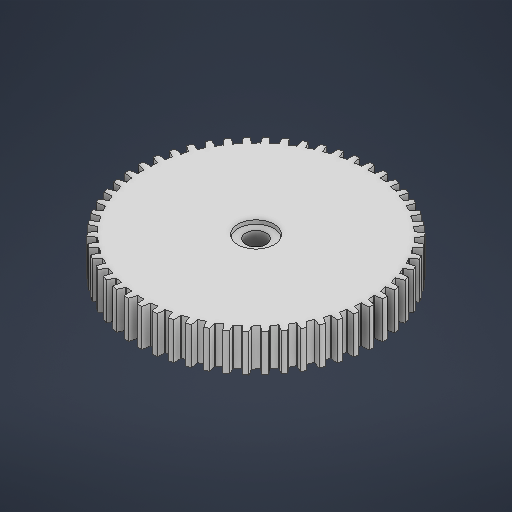
# Autodesk Inventor part: Servo Wheel
Saved by Autodesk Inventor 2027 (Build 310192060, 192F)
## iProperties
Created: 2026-10-23
Part Number: Servo Wheel
Material: Generic
Document SubType Name: Modeling
Designer: troop
Density: 1 g/cm^3
Appearance: Default
Author: troop
Autodesk Inventor part; units mm, degrees
(part 1 of 2)
ref_plane "YZ Plane" through (0, 0, 0) normal (1, 0, 0) x (0, 1, 0)
ref_plane "XZ Plane" through (0, 0, 0) normal (0, 1, 0) x (-1, 0, 0)
sketch "Sketch1" plane through (0, 0, 0) normal (0, 1, 0) x (-1, 0, 0)
  circle A0 centre (0, 0) radius 15
  dimension "d0" = 30
  constraints: 1 centre point, 1 coincident
  measures "d0" diameter of A0
extrude "Extrusion1" add sketch "Sketch1" along normal blind 5
sketch "Sketch2" plane through (0, 0, 0) normal (0, -1, 0) x (1, 0, 0)
  line L0 (-2.242, 0) -> (-2.6661, 0.4202)
  line L1 (-2.242, 0) -> (-2.6619, -0.4271)
  line L2 (-2.1323, -0.6928) -> (-2.6654, -0.4242)
  line L3 (-2.1323, -0.6928) -> (-2.3997, -1.2288)
  line L4 (-1.8138, -1.3178) -> (-2.4039, -1.2272)
  line L5 (-1.8138, -1.3178) -> (-1.9025, -1.9102)
  line L6 (-1.3178, -1.8138) -> (-1.907, -1.9099)
  line L7 (-1.3178, -1.8138) -> (-1.2191, -2.4046)
  line L8 (-0.6928, -2.1323) -> (-1.2235, -2.4058)
  line L9 (-0.6928, -2.1323) -> (-0.4164, -2.6637)
  line L10 (0, -2.242) -> (-0.4202, -2.6661)
  line L11 (0, -2.242) -> (0.4271, -2.6619)
  line L12 (0.6928, -2.1323) -> (0.4242, -2.6654)
  line L13 (0.6928, -2.1323) -> (1.2288, -2.3997)
  line L14 (1.3178, -1.8138) -> (1.2272, -2.4039)
  line L15 (1.3178, -1.8138) -> (1.9102, -1.9025)
  line L16 (1.8138, -1.3178) -> (1.9099, -1.907)
  line L17 (1.8138, -1.3178) -> (2.4046, -1.2191)
  line L18 (2.1323, -0.6928) -> (2.4058, -1.2235)
  line L19 (2.1323, -0.6928) -> (2.6637, -0.4164)
  line L20 (2.242, 0) -> (2.6661, -0.4202)
  line L21 (2.242, 0) -> (2.6619, 0.4271)
  line L22 (2.1323, 0.6928) -> (2.6654, 0.4242)
  line L23 (2.1323, 0.6928) -> (2.3997, 1.2288)
  line L24 (1.8138, 1.3178) -> (2.4039, 1.2272)
  line L25 (1.8138, 1.3178) -> (1.9025, 1.9102)
  line L26 (1.3178, 1.8138) -> (1.907, 1.9099)
  line L27 (1.3178, 1.8138) -> (1.2191, 2.4046)
  line L28 (0.6928, 2.1323) -> (1.2235, 2.4058)
  line L29 (0.6928, 2.1323) -> (0.4164, 2.6637)
  line L30 (0, 2.242) -> (0.4202, 2.6661)
  line L31 (0, 2.242) -> (-0.4271, 2.6619)
  line L32 (-0.6928, 2.1323) -> (-0.4242, 2.6654)
  line L33 (-0.6928, 2.1323) -> (-1.2288, 2.3997)
  line L34 (-1.3178, 1.8138) -> (-1.2272, 2.4039)
  line L35 (-1.3178, 1.8138) -> (-1.9102, 1.9025)
  line L36 (-1.8138, 1.3178) -> (-1.9099, 1.907)
  line L37 (-1.8138, 1.3178) -> (-2.4046, 1.2191)
  line L38 (-2.1323, 0.6928) -> (-2.4058, 1.2235)
  line L39 (-2.1323, 0.6928) -> (-2.6637, 0.4164)
  point P0 (0, 0)
  point P1 (-2.6627, 0.4168)
  point P2 (-2.6612, -0.4264)
  point P3 (-2.3992, -1.2279)
  point P4 (-1.9023, -1.9092)
  point P5 (-1.2193, -2.4036)
  point P6 (-0.4168, -2.6627)
  point P7 (0.4264, -2.6612)
  point P8 (1.2279, -2.3992)
  point P9 (1.9092, -1.9023)
  point P10 (2.4036, -1.2193)
  point P11 (2.6627, -0.4168)
  point P12 (2.6612, 0.4264)
  point P13 (2.3992, 1.2279)
  point P14 (1.9023, 1.9092)
  point P15 (1.2193, 2.4036)
  point P16 (0.4168, 2.6627)
  point P17 (-0.4264, 2.6612)
  point P18 (-1.2279, 2.3992)
  point P19 (-1.9092, 1.9023)
  point P20 (-2.4036, 1.2193)
  dimension "d3" = 2.242
  dimension "d5" = 2.699
  dimension "d6" = 0.597
  dimension "d7" = 0
  dimension "d8" = 0.599
  dimension "d9" = 2.696
  dimension "d12" = 360
  constraints: 80 end point, 101 other
  measures "d3" distance of point (0, 0) L0.start
  measures "d5" distance of L0.end point (0, 0)
  measures "d6" distance of L0.start L0.end
  measures "d7" vertical distance of point (0, 0) L0.start
  measures "d8" distance of L0.start L1.end
  measures "d9" distance of point (0, 0) L1.end
ref_plane "Work Plane1" through (0, 2, 0) normal (0, -1, 0) x (1, 0, 0)
sketch "Sketch3" plane through (0, 2, 0) normal (0, -1, 0) x (1, 0, 0)
  circle A0 centre (0, 0) radius 1.3518
  dimension "d16" = 2.7035
  constraints: 1 centre point, 1 coincident
  measures "d16" diameter of A0
sketch "Sketch4" plane through (0, 5, 0) normal (0, 1, 0) x (1, 0, 0)
  circle A0 centre (0, 0) radius 2.398
  dimension "d19" = 4.796
  constraints: 1 centre point, 1 coincident
  measures "d19" diameter of A0
sketch "Sketch5" plane through (0, 5, 0) normal (0, 1, 0) x (1, 0, 0)
  line L0 (15.0507, 0.0003) -> (14.984, 0.8109)
  line L1 (15.0507, 0.0003) -> (14.9793, -0.8668)
  arc A0 (15.0506, 0.035) -> (15.0877, -0.0001) centre (15.108, 0.0585) ccw
  arc A1 (16.0355, -0.2257) -> (15.0877, -0.0001) centre (14.1946, -5.8554) ccw
  line L2 (15.0877, -0.0001) -> (15.016, -0.8698)
  arc A2 (15.016, -0.8698) -> (15.9859, -0.828) centre (15.2464, 5.0487) ccw
  line L3 (16.0355, -0.2257) -> (15.9859, -0.828)
  line L4 (14.9793, -0.8668) -> (14.975, -0.9188)
  arc A3 (15.016, -0.8698) -> (14.965, -0.9233) centre (15.0507, -0.954) ccw
  line L5 (14.984, 0.8109) -> (14.9832, 0.8205)
  line L6 (14.9832, 0.8205) -> (14.9811, 0.8459)
  arc A4 (15.0467, 0.0489) -> (15.0506, 0.035) centre (15.108, 0.0585) ccw
  line L7 (14.9786, 0.8781) -> (14.9804, 0.8259)
  arc A5 (15.0154, 0.8793) -> (14.971, 0.8203) centre (15.0597, 0.7998) ccw
  arc A6 (15.0154, 0.8793) -> (15.9739, 1.0335) centre (14.5572, 6.7846) ccw
  line L8 (14.9489, 1.7476) -> (14.9786, 0.8781)
  line L9 (14.9857, 1.7515) -> (15.0154, 0.8793)
  line L10 (15.9533, 1.6374) -> (15.9739, 1.0335)
  arc A7 (14.9448, 1.782) -> (14.9857, 1.7515) centre (14.999, 1.812) ccw
  arc A8 (14.9393, 1.7954) -> (14.9448, 1.782) centre (14.999, 1.812) ccw
  arc A9 (15.9533, 1.6374) -> (14.9857, 1.7515) centre (14.7783, -4.1679) ccw
  line L11 (14.9489, 1.7476) -> (14.7885, 2.545)
  line L12 (14.7885, 2.545) -> (14.7866, 2.5544)
  line L13 (14.7866, 2.5544) -> (14.7816, 2.5794)
  line L14 (14.7754, 2.611) -> (14.7832, 2.5594)
  arc A10 (14.8118, 2.6166) -> (14.7745, 2.5528) centre (14.865, 2.5427) ccw
  arc A11 (14.8118, 2.6166) -> (15.7459, 2.8809) centre (13.6711, 8.4287) ccw
  line L15 (14.645, 3.4712) -> (14.7754, 2.611)
  line L16 (14.681, 3.4794) -> (14.8118, 2.6166)
  line L17 (15.6553, 3.4784) -> (15.7459, 2.8809)
  arc A12 (14.6368, 3.5049) -> (14.681, 3.4794) centre (14.6872, 3.5411) ccw
  arc A13 (14.6299, 3.5176) -> (14.6368, 3.5049) centre (14.6872, 3.5411) ccw
  arc A14 (15.6553, 3.4784) -> (14.681, 3.4794) centre (15.1623, -2.424) ccw
  line L18 (14.645, 3.4712) -> (14.3931, 4.2446)
  line L19 (14.3931, 4.2446) -> (14.3901, 4.2538)
  line L20 (14.3901, 4.2538) -> (14.3822, 4.278)
  line L21 (14.3724, 4.3087) -> (14.3861, 4.2583)
  arc A15 (14.4079, 4.3184) -> (14.3783, 4.2507) centre (14.4693, 4.2512) ccw
  arc A16 (14.4079, 4.3184) -> (15.305, 4.6895) centre (12.6002, 9.9588) ccw
  line L22 (14.143, 5.1479) -> (14.3724, 4.3087)
  line L23 (14.1778, 5.1602) -> (14.4079, 4.3184)
  line L24 (15.1456, 5.2723) -> (15.305, 4.6895)
  arc A17 (14.131, 5.1805) -> (14.1778, 5.1602) centre (14.1768, 5.2222) ccw
  arc A18 (14.1226, 5.1922) -> (14.131, 5.1805) centre (14.1768, 5.2222) ccw
  arc A19 (15.1456, 5.2723) -> (14.1778, 5.1602) centre (15.3412, -0.6474) ccw
  line L25 (14.143, 5.1479) -> (13.803, 5.8868)
  line L26 (13.803, 5.8868) -> (13.799, 5.8956)
  line L27 (13.799, 5.8956) -> (13.7883, 5.9187)
  line L28 (13.775, 5.9481) -> (13.7945, 5.8997)
  arc A20 (13.8092, 5.9619) -> (13.7876, 5.8912) centre (13.8779, 5.9022) ccw
  arc A21 (13.8092, 5.9619) -> (14.6571, 6.4345) centre (11.3588, 11.3542) ccw
  line L29 (13.4497, 6.755) -> (13.775, 5.9481)
  line L30 (13.4829, 6.7713) -> (13.8092, 5.9619)
  line L31 (14.4311, 6.995) -> (14.6571, 6.4345)
  arc A22 (13.434, 6.786) -> (13.4829, 6.7713) centre (13.4747, 6.8327) ccw
  arc A23 (13.4243, 6.7966) -> (13.434, 6.786) centre (13.4747, 6.8327) ccw
  arc A24 (14.4311, 6.995) -> (13.4829, 6.7713) centre (15.3126, 1.138) ccw
  line L32 (13.4497, 6.755) -> (13.0262, 7.4495)
  line L33 (13.0262, 7.4495) -> (13.0212, 7.4577)
  line L34 (13.0212, 7.4577) -> (13.008, 7.4794)
  line L35 (12.9913, 7.507) -> (13.0163, 7.4612)
  arc A25 (13.0237, 7.5247) -> (13.0104, 7.452) centre (13.0989, 7.4735) ccw
  arc A26 (13.0237, 7.5247) -> (13.811, 8.0926) centre (9.9639, 12.5961) ccw
  line L36 (12.5745, 8.2707) -> (12.9913, 7.507)
  line L37 (12.6056, 8.2907) -> (13.0237, 7.5247)
  line L38 (13.5215, 8.6231) -> (13.811, 8.0926)
  arc A27 (12.5554, 8.2997) -> (12.6056, 8.2907) centre (12.5904, 8.3508) ccw
  arc A28 (12.5445, 8.3091) -> (12.5554, 8.2997) centre (12.5904, 8.3508) ccw
  arc A29 (13.5215, 8.6231) -> (12.6056, 8.2907) centre (15.077, 2.9079) ccw
  line L39 (12.5745, 8.2707) -> (12.0733, 8.9114)
  line L40 (12.0733, 8.9114) -> (12.0674, 8.9189)
  line L41 (12.0674, 8.9189) -> (12.0517, 8.939)
  line L42 (12.0319, 8.9645) -> (12.0621, 8.9219)
  arc A30 (12.062, 8.9858) -> (12.0573, 8.912) centre (12.1427, 8.9436) ccw
  arc A31 (12.062, 8.9858) -> (12.7781, 9.6413) centre (8.4342, 13.6677) ccw
  line L43 (11.5293, 9.6746) -> (12.0319, 8.9645)
  line L44 (11.5579, 9.6981) -> (12.062, 8.9858)
  line L45 (12.429, 10.1345) -> (12.7781, 9.6413)
  arc A32 (11.5069, 9.7011) -> (11.5579, 9.6981) centre (11.5358, 9.756) ccw
  arc A33 (11.495, 9.7093) -> (11.5069, 9.7011) centre (11.5358, 9.756) ccw
  arc A34 (12.429, 10.1345) -> (11.5579, 9.6981) centre (14.6374, 4.6386) ccw
  line L46 (11.5293, 9.6746) -> (10.9571, 10.2527)
  line L47 (10.9571, 10.2527) -> (10.9504, 10.2596)
  line L48 (10.9504, 10.2596) -> (10.9325, 10.2777)
  line L49 (10.9099, 10.3007) -> (10.9448, 10.2619)
  arc A35 (10.9373, 10.3253) -> (10.9412, 10.2515) centre (11.0223, 10.2928) ccw
  arc A36 (10.9373, 10.3253) -> (11.5724, 11.0595) centre (6.7904, 14.5544) ccw
  line L50 (10.3282, 10.9477) -> (10.9099, 10.3007)
  line L51 (10.3539, 10.9743) -> (10.9373, 10.3253)
  line L52 (11.1684, 11.5089) -> (11.5724, 11.0595)
  arc A37 (10.3029, 10.9714) -> (10.3539, 10.9743) centre (10.3252, 11.0293) ccw
  arc A38 (10.2901, 10.9781) -> (10.3029, 10.9714) centre (10.3252, 11.0293) ccw
  arc A39 (11.1684, 11.5089) -> (10.3539, 10.9743) centre (13.9999, 6.3065) ccw
  line L53 (10.3282, 10.9477) -> (9.6928, 11.4554)
  line L54 (9.6928, 11.4554) -> (9.6853, 11.4615)
  line L55 (9.6853, 11.4615) -> (9.6654, 11.4774)
  line L56 (9.6403, 11.4976) -> (9.6794, 11.4631)
  arc A40 (9.6646, 11.5253) -> (9.6771, 11.4524) centre (9.7528, 11.5028) ccw
  arc A41 (9.6646, 11.5253) -> (10.2102, 12.3282) centre (5.0548, 15.2443) ccw
  line L57 (8.9874, 12.0727) -> (9.6403, 11.4976)
  line L58 (9.0098, 12.1021) -> (9.6646, 11.5253)
  line L59 (9.7568, 12.7276) -> (10.2102, 12.3282)
  arc A42 (8.9595, 12.0933) -> (9.0098, 12.1021) centre (8.9749, 12.1534) ccw
  arc A43 (8.9461, 12.0985) -> (8.9595, 12.0933) centre (8.9749, 12.1534) ccw
  arc A44 (9.7568, 12.7276) -> (9.0098, 12.1021) centre (13.1731, 7.8892) ccw
  line L60 (8.9874, 12.0727) -> (8.2974, 12.5033)
  line L61 (8.2974, 12.5033) -> (8.2892, 12.5084)
  line L62 (8.2892, 12.5084) -> (8.2676, 12.5218)
  line L63 (8.2403, 12.539) -> (8.2832, 12.5093)
  arc A45 (8.2613, 12.5693) -> (8.2821, 12.4984) centre (8.3515, 12.5573) ccw
  arc A46 (8.2613, 12.5693) -> (8.71, 13.4302) centre (3.2509, 15.7281) ccw
  line L64 (7.5251, 13.0344) -> (8.2403, 12.539)
  line L65 (7.5439, 13.0663) -> (8.2613, 12.5693)
  line L66 (8.2132, 13.7743) -> (8.71, 13.4302)
  arc A47 (7.495, 13.0517) -> (7.5439, 13.0663) centre (7.5033, 13.1131) ccw
  arc A48 (7.481, 13.0553) -> (7.495, 13.0517) centre (7.5033, 13.1131) ccw
  arc A49 (8.2132, 13.7743) -> (7.5439, 13.0663) centre (12.1682, 9.3652) ccw
  line L67 (7.5251, 13.0344) -> (6.7897, 13.382)
  line L68 (6.7897, 13.382) -> (6.781, 13.3861)
  line L69 (6.781, 13.3861) -> (6.758, 13.397)
  line L70 (6.7289, 13.4109) -> (6.775, 13.3863)
  arc A50 (6.7462, 13.4434) -> (6.7751, 13.3754) centre (6.8372, 13.4419) ccw
  arc A51 (6.7462, 13.4434) -> (7.0919, 14.3505) centre (1.403, 15.9992) ccw
  line L71 (5.961, 13.8199) -> (6.7289, 13.4109)
  line L72 (5.976, 13.8537) -> (6.7462, 13.4434)
  line L73 (6.5586, 14.6346) -> (7.0919, 14.3505)
  arc A52 (5.9291, 13.8336) -> (5.976, 13.8537) centre (5.9303, 13.8955) ccw
  arc A53 (5.9148, 13.8355) -> (5.9291, 13.8336) centre (5.9303, 13.8955) ccw
  arc A54 (6.5586, 14.6346) -> (5.976, 13.8537) centre (10.9987, 10.7145) ccw
  line L74 (5.961, 13.8199) -> (5.1902, 14.0797)
  line L75 (5.1902, 14.0797) -> (5.1811, 14.0828)
  line L76 (5.1811, 14.0828) -> (5.157, 14.0909)
  line L77 (5.1265, 14.1014) -> (5.1751, 14.0823)
  arc A55 (5.1399, 14.1357) -> (5.1765, 14.0715) centre (5.2305, 14.1448) ccw
  arc A56 (5.1399, 14.1357) -> (5.378, 15.0768) centre (-0.4639, 16.0539) ccw
  line L78 (4.3163, 14.4185) -> (5.1265, 14.1014)
  line L79 (4.3273, 14.4538) -> (5.1399, 14.1357)
  line L80 (4.8153, 15.2971) -> (5.378, 15.0768)
  arc A57 (4.283, 14.4284) -> (4.3273, 14.4538) centre (4.277, 14.4901) ccw
  arc A58 (4.2686, 14.4286) -> (4.283, 14.4284) centre (4.277, 14.4901) ccw
  arc A59 (4.8153, 15.2971) -> (4.3273, 14.4538) centre (9.6804, 11.9189) ccw
  line L81 (4.3163, 14.4185) -> (3.5206, 14.5871)
  line L82 (3.5206, 14.5871) -> (3.5112, 14.5891)
  line L83 (3.5112, 14.5891) -> (3.4863, 14.5944)
  line L84 (3.4547, 14.6012) -> (3.5052, 14.5879)
  arc A60 (3.4641, 14.6368) -> (3.5079, 14.5773) centre (3.553, 14.6564) ccw
  arc A61 (3.4641, 14.6368) -> (3.5913, 15.5992) centre (-2.3245, 15.8915) ccw
  line L85 (2.6133, 14.8221) -> (3.4547, 14.6012)
  line L86 (2.62, 14.8584) -> (3.4641, 14.6368)
  line L87 (3.0068, 15.7527) -> (3.5913, 15.5992)
  arc A62 (2.5791, 14.828) -> (2.62, 14.8584) centre (2.5659, 14.8886) ccw
  arc A63 (2.5647, 14.8266) -> (2.5791, 14.828) centre (2.5659, 14.8886) ccw
  arc A64 (3.0068, 15.7527) -> (2.62, 14.8584) centre (8.2313, 12.9621) ccw
  line L88 (2.6133, 14.8221) -> (1.8033, 14.8972)
  line L89 (1.8033, 14.8972) -> (1.7937, 14.8981)
  line L90 (1.7937, 14.8981) -> (1.7684, 14.9004)
  line L91 (1.7363, 14.9035) -> (1.788, 14.8962)
  arc A65 (1.7415, 14.94) -> (1.7919, 14.886) centre (1.8275, 14.9697) ccw
  arc A66 (1.7415, 14.94) -> (1.7561, 15.9107) centre (-4.1537, 15.5141) ccw
  line L92 (0.8748, 15.0253) -> (1.7363, 14.9035)
  line L93 (0.8774, 15.0621) -> (1.7415, 14.94)
  line L94 (1.1577, 15.9952) -> (1.7561, 15.9107)
  arc A67 (0.8402, 15.0272) -> (0.8774, 15.0621) centre (0.8201, 15.0858) ccw
  arc A68 (0.8261, 15.0241) -> (0.8402, 15.0272) centre (0.8201, 15.0858) ccw
  arc A69 (1.1577, 15.9952) -> (0.8774, 15.0621) centre (6.6708, 13.8301) ccw
  line L95 (0.8748, 15.0253) -> (0.0617, 15.0058)
  line L96 (0.0617, 15.0058) -> (0.0521, 15.0056)
  line L97 (0.0521, 15.0056) -> (0.0266, 15.0049)
  line L98 (-0.0056, 15.0043) -> (0.0465, 15.0031)
  arc A70 (-0.0048, 15.0412) -> (0.0516, 14.9934) centre (0.0772, 15.0807) ccw
  arc A71 (-0.0048, 15.0412) -> (-0.1029, 16.0069) centre (-5.9267, 14.927) ccw
  line L99 (-0.8754, 15.0252) -> (-0.0056, 15.0043)
  line L100 (-0.8772, 15.0621) -> (-0.0048, 15.0412)
  line L101 (-0.707, 16.0215) -> (-0.1029, 16.0069)
  arc A72 (-0.91, 15.0231) -> (-0.8772, 15.0621) centre (-0.9368, 15.079) ccw
  arc A73 (-0.9237, 15.0184) -> (-0.91, 15.0231) centre (-0.9368, 15.079) ccw
  arc A74 (-0.707, 16.0215) -> (-0.8772, 15.0621) centre (5.0201, 14.511) ccw
  line L102 (-0.8754, 15.0252) -> (-1.6808, 14.9115)
  line L103 (-1.6808, 14.9115) -> (-1.6903, 14.9101)
  line L104 (-1.6903, 14.9101) -> (-1.7155, 14.9066)
  line L105 (-1.7475, 14.9022) -> (-1.6955, 14.907)
  arc A75 (-1.7509, 14.9389) -> (-1.6894, 14.898) centre (-1.6741, 14.9877) ccw
  arc A76 (-1.7509, 14.9389) -> (-1.9605, 15.8868) centre (-7.6195, 14.1381) ccw
  line L106 (-2.6138, 14.822) -> (-1.7475, 14.9022)
  line L107 (-2.6199, 14.8585) -> (-1.7509, 14.9389)
  line L108 (-2.5622, 15.8311) -> (-1.9605, 15.8868)
  arc A77 (-2.648, 14.8159) -> (-2.6199, 14.8585) centre (-2.6811, 14.8683) ccw
  arc A78 (-2.661, 14.8096) -> (-2.648, 14.8159) centre (-2.6811, 14.8683) ccw
  arc A79 (-2.5622, 15.8311) -> (-2.6199, 14.8585) centre (3.3016, 14.9957) ccw
  line L109 (-2.6138, 14.822) -> (-3.4005, 14.6155)
  line L110 (-3.4005, 14.6155) -> (-3.4099, 14.6131)
  line L111 (-3.4099, 14.6131) -> (-3.4345, 14.6066)
  line L112 (-3.4657, 14.5986) -> (-3.4147, 14.6094)
  arc A80 (-3.4734, 14.6346) -> (-3.4075, 14.6011) centre (-3.4027, 14.692) ccw
  arc A81 (-3.4734, 14.6346) -> (-3.7916, 15.5517) centre (-9.2093, 13.1579) ccw
  line L113 (-4.3169, 14.4184) -> (-3.4657, 14.5986)
  line L114 (-4.3271, 14.4539) -> (-3.4734, 14.6346)
  line L115 (-4.3828, 15.4266) -> (-3.7916, 15.5517)
  arc A82 (-4.3501, 14.4083) -> (-4.3271, 14.4539) centre (-4.389, 14.4565) ccw
  arc A83 (-4.3623, 14.4006) -> (-4.3501, 14.4083) centre (-4.389, 14.4565) ccw
  arc A84 (-4.3828, 15.4266) -> (-4.3271, 14.4539) centre (1.5383, 15.2776) ccw
  line L116 (-4.3169, 14.4184) -> (-5.0743, 14.1219)
  line L117 (-5.0743, 14.1219) -> (-5.0833, 14.1184)
  line L118 (-5.0833, 14.1184) -> (-5.107, 14.1091)
  line L119 (-5.1371, 14.0975) -> (-5.0876, 14.1142)
  arc A85 (-5.1488, 14.1324) -> (-5.0795, 14.1068) centre (-5.0853, 14.1976) ccw
  arc A86 (-5.1488, 14.1324) -> (-5.5714, 15.0064) centre (-10.6746, 11.9998) ccw
  line L120 (-5.9615, 13.8197) -> (-5.1371, 14.0975)
  line L121 (-5.9758, 13.8538) -> (-5.1488, 14.1324)
  line L122 (-6.1441, 14.8134) -> (-5.5714, 15.0064)
  arc A87 (-5.9934, 13.8058) -> (-5.9758, 13.8538) centre (-6.0377, 13.8492) ccw
  arc A88 (-6.0046, 13.7968) -> (-5.9934, 13.8058) centre (-6.0377, 13.8492) ccw
  arc A89 (-6.1441, 14.8134) -> (-5.9758, 13.8538) centre (-0.2457, 15.3529) ccw
  line L123 (-5.9615, 13.8197) -> (-6.6795, 13.4373)
  line L124 (-6.6795, 13.4373) -> (-6.688, 13.4328)
  line L125 (-6.688, 13.4328) -> (-6.7104, 13.4208)
  line L126 (-6.739, 13.4058) -> (-6.6918, 13.4281)
  arc A90 (-6.7547, 13.4391) -> (-6.6829, 13.4217) centre (-6.6992, 13.5112) ccw
  arc A91 (-6.7547, 13.4391) -> (-7.2759, 14.2581) centre (-11.9955, 10.6794) ccw
  line L127 (-7.5256, 13.0342) -> (-6.739, 13.4058)
  line L128 (-7.5438, 13.0664) -> (-6.7547, 13.4391)
  line L129 (-7.8223, 14) -> (-7.2759, 14.2581)
  arc A92 (-7.5556, 13.0167) -> (-7.5438, 13.0664) centre (-7.6046, 13.0546) ccw
  arc A93 (-7.5657, 13.0064) -> (-7.5556, 13.0167) centre (-7.6046, 13.0546) ccw
  arc A94 (-7.8223, 14) -> (-7.5438, 13.0664) centre (-2.0264, 15.2205) ccw
  line L130 (-7.5256, 13.0342) -> (-8.1943, 12.5711)
  line L131 (-8.1943, 12.5711) -> (-8.2022, 12.5656)
  line L132 (-8.2022, 12.5656) -> (-8.2231, 12.5511)
  line L133 (-8.2497, 12.5328) -> (-8.2054, 12.5605)
  arc A95 (-8.2692, 12.5641) -> (-8.1959, 12.5551) centre (-8.2225, 12.6422) ccw
  arc A96 (-8.2692, 12.5641) -> (-8.882, 13.317) centre (-13.1542, 9.2146) ccw
  line L134 (-8.9879, 12.0724) -> (-8.2497, 12.5328)
  line L135 (-9.0097, 12.1022) -> (-8.2692, 12.5641)
  line L136 (-9.3947, 12.9972) -> (-8.882, 13.317)
  arc A97 (-9.0157, 12.0515) -> (-9.0097, 12.1022) centre (-9.0688, 12.0835) ccw
  arc A98 (-9.0245, 12.0401) -> (-9.0157, 12.0515) centre (-9.0688, 12.0835) ccw
  arc A99 (-9.3947, 12.9972) -> (-9.0097, 12.1022) centre (-3.7797, 14.8824) ccw
  line L137 (-8.9879, 12.0724) -> (-9.5983, 11.5348)
  line L138 (-9.5983, 11.5348) -> (-9.6055, 11.5284)
  line L139 (-9.6055, 11.5284) -> (-9.6246, 11.5116)
  line L140 (-9.6489, 11.4903) -> (-9.6081, 11.5229)
  arc A100 (-9.6719, 11.5191) -> (-9.598, 11.5187) centre (-9.6345, 11.6021) ccw
  arc A101 (-9.6719, 11.5191) -> (-10.3679, 12.1959) centre (-14.135, 7.6252) ccw
  line L141 (-10.3286, 10.9473) -> (-9.6489, 11.4903)
  line L142 (-10.3537, 10.9744) -> (-9.6719, 11.5191)
  line L143 (-10.84, 11.8187) -> (-10.3679, 12.1959)
  arc A102 (-10.3538, 10.9234) -> (-10.3537, 10.9744) centre (-10.4103, 10.949) ccw
  arc A103 (-10.3612, 10.911) -> (-10.3538, 10.9234) centre (-10.4103, 10.949) ccw
  arc A104 (-10.84, 11.8187) -> (-10.3537, 10.9744) centre (-5.4819, 14.3429) ccw
  line L144 (-10.3286, 10.9473) -> (-10.8725, 10.3425)
  line L145 (-10.8725, 10.3425) -> (-10.8789, 10.3353)
  line L146 (-10.8789, 10.3353) -> (-10.8959, 10.3164)
  line L147 (-10.9176, 10.2925) -> (-10.8809, 10.3296)
  arc A105 (-10.9438, 10.3184) -> (-10.8704, 10.3266) centre (-10.9163, 10.4052) ccw
  arc A106 (-10.9438, 10.3184) -> (-11.7137, 10.9098) centre (-14.9246, 5.9327) ccw
  line L148 (-11.5297, 9.6742) -> (-10.9176, 10.2925)
  line L149 (-11.5578, 9.6982) -> (-10.9438, 10.3184)
  line L150 (-12.1388, 10.4803) -> (-11.7137, 10.9098)
  arc A107 (-11.5519, 9.6475) -> (-11.5578, 9.6982) centre (-11.611, 9.6664) ccw
  arc A108 (-11.5579, 9.6344) -> (-11.5519, 9.6475) centre (-11.611, 9.6664) ccw
  arc A109 (-12.1388, 10.4803) -> (-11.5578, 9.6982) centre (-7.1099, 13.6096) ccw
  line L151 (-11.5297, 9.6742) -> (-11.9997, 9.0103)
  line L152 (-11.9997, 9.0103) -> (-12.0052, 9.0025)
  line L153 (-12.0052, 9.0025) -> (-12.0199, 8.9817)
  line L154 (-12.0387, 8.9554) -> (-12.0065, 8.9965)
  arc A110 (-12.0677, 8.9781) -> (-11.9957, 8.9948) centre (-12.0505, 9.0675) ccw
  arc A111 (-12.0677, 8.9781) -> (-12.901, 9.4761) centre (-15.5125, 4.1599) ccw
  line L155 (-12.5748, 8.2703) -> (-12.0387, 8.9554)
  line L156 (-12.6055, 8.2909) -> (-12.0677, 8.9781)
  line L157 (-13.2734, 9.0002) -> (-12.901, 9.4761)
  arc A112 (-12.5938, 8.2412) -> (-12.6055, 8.2909) centre (-12.6547, 8.2531) ccw
  arc A113 (-12.5982, 8.2275) -> (-12.5938, 8.2412) centre (-12.6547, 8.2531) ccw
  arc A114 (-13.2734, 9.0002) -> (-12.6055, 8.2909) centre (-8.6418, 12.6921) ccw
  line L158 (-12.5748, 8.2703) -> (-12.9646, 7.5563)
  line L159 (-12.9646, 7.5563) -> (-12.9692, 7.5479)
  line L160 (-12.9692, 7.5479) -> (-12.9814, 7.5255)
  line L161 (-12.9969, 7.4973) -> (-12.9698, 7.5418)
  arc A115 (-13.0284, 7.5165) -> (-12.9588, 7.5414) centre (-13.0216, 7.6072) ccw
  arc A116 (-13.0284, 7.5165) -> (-13.9139, 7.9143) centre (-15.8905, 2.3309) ccw
  line L162 (-13.4499, 6.7545) -> (-12.9969, 7.4973)
  line L163 (-13.4828, 6.7714) -> (-13.0284, 7.5165)
  line L164 (-14.2285, 7.3984) -> (-13.9139, 7.9143)
  arc A117 (-13.4654, 6.7234) -> (-13.4828, 6.7714) centre (-13.5272, 6.7282) ccw
  arc A118 (-13.4682, 6.7093) -> (-13.4654, 6.7234) centre (-13.5272, 6.7282) ccw
  arc A119 (-14.2285, 7.3984) -> (-13.4828, 6.7714) centre (-10.0568, 11.6031) ccw
  line L165 (-13.4499, 6.7545) -> (-13.7541, 6.0001)
  line L166 (-13.7541, 6.0001) -> (-13.7577, 5.9912)
  line L167 (-13.7577, 5.9912) -> (-13.7672, 5.9676)
  line L168 (-13.7794, 5.9377) -> (-13.7576, 5.9852)
  arc A120 (-13.8129, 5.9531) -> (-13.7467, 5.9859) centre (-13.8167, 6.0441) ccw
  arc A121 (-13.8129, 5.9531) -> (-14.7386, 6.2455) centre (-16.0537, 0.4703) ccw
  line L169 (-14.1431, 5.1474) -> (-13.7794, 5.9377)
  line L170 (-14.1777, 5.1604) -> (-13.8129, 5.9531)
  line L171 (-14.9912, 5.6966) -> (-14.7386, 6.2455)
  arc A122 (-14.1549, 5.1147) -> (-14.1777, 5.1604) centre (-14.2169, 5.1123) ccw
  arc A123 (-14.156, 5.1004) -> (-14.1549, 5.1147) centre (-14.2169, 5.1123) ccw
  arc A124 (-14.9912, 5.6966) -> (-14.1777, 5.1604) centre (-11.3359, 10.3571) ccw
  line L172 (-14.1431, 5.1474) -> (-14.3577, 4.3628)
  line L173 (-14.3577, 4.3628) -> (-14.3602, 4.3535)
  line L174 (-14.3602, 4.3535) -> (-14.367, 4.329)
  line L175 (-14.3756, 4.2979) -> (-14.3594, 4.3475)
  arc A125 (-14.4106, 4.3093) -> (-14.3487, 4.3496) centre (-14.425, 4.3992) ccw
  arc A126 (-14.4106, 4.3093) -> (-15.364, 4.4922) centre (-15.9997, -1.3966) ccw
  line L176 (-14.6451, 3.4707) -> (-14.3756, 4.2979)
  line L177 (-14.681, 3.4795) -> (-14.4106, 4.3093)
  line L178 (-15.5512, 3.9177) -> (-15.364, 4.4922)
  arc A127 (-14.653, 3.4369) -> (-14.681, 3.4795) centre (-14.7142, 3.4272) ccw
  arc A128 (-14.6524, 3.4225) -> (-14.653, 3.4369) centre (-14.7142, 3.4272) ccw
  arc A129 (-15.5512, 3.9177) -> (-14.681, 3.4795) centre (-12.4616, 8.971) ccw
  line L179 (-14.6451, 3.4707) -> (-14.7671, 2.6665)
  line L180 (-14.7671, 2.6665) -> (-14.7685, 2.657)
  line L181 (-14.7685, 2.657) -> (-14.7724, 2.6318)
  line L182 (-14.7774, 2.5999) -> (-14.7671, 2.6511)
  arc A130 (-14.8135, 2.6072) -> (-14.7566, 2.6544) centre (-14.8382, 2.6948) ccw
  arc A131 (-14.8135, 2.6072) -> (-15.7816, 2.6782) centre (-15.7294, -3.2446) ccw
  line L183 (-14.949, 1.747) -> (-14.7774, 2.5999)
  line L184 (-14.9856, 1.7517) -> (-14.8135, 2.6072)
  line L185 (-15.9009, 2.0858) -> (-15.7816, 2.6782)
  arc A132 (-14.9529, 1.7125) -> (-14.9856, 1.7517) centre (-15.0126, 1.6958) ccw
  arc A133 (-14.9507, 1.6983) -> (-14.9529, 1.7125) centre (-15.0126, 1.6958) ccw
  arc A134 (-15.9009, 2.0858) -> (-14.9856, 1.7517) centre (-13.4188, 7.4637) ccw
  line L186 (-14.949, 1.747) -> (-14.9768, 0.9341)
  line L187 (-14.9768, 0.9341) -> (-14.9771, 0.9245)
  line L188 (-14.9771, 0.9245) -> (-14.978, 0.899)
  line L189 (-14.9793, 0.8668) -> (-14.975, 0.9188)
  arc A135 (-15.016, 0.8698) -> (-14.965, 0.9233) centre (-15.0507, 0.954) ccw
  arc A136 (-15.016, 0.8698) -> (-15.9859, 0.828) centre (-15.2464, -5.0487) ccw
  line L190 (-15.0507, -0.0003) -> (-14.9793, 0.8668)
  line L191 (-15.0877, 0.0001) -> (-15.016, 0.8698)
  line L192 (-16.0355, 0.2257) -> (-15.9859, 0.828)
  arc A137 (-15.0506, -0.035) -> (-15.0877, 0.0001) centre (-15.108, -0.0585) ccw
  arc A138 (-15.0467, -0.0489) -> (-15.0506, -0.035) centre (-15.108, -0.0585) ccw
  arc A139 (-16.0355, 0.2257) -> (-15.0877, 0.0001) centre (-14.1946, 5.8554) ccw
  line L193 (-15.0507, -0.0003) -> (-14.984, -0.8109)
  line L194 (-14.984, -0.8109) -> (-14.9832, -0.8205)
  line L195 (-14.9832, -0.8205) -> (-14.9811, -0.8459)
  line L196 (-14.9786, -0.8781) -> (-14.9804, -0.8259)
  arc A140 (-15.0154, -0.8793) -> (-14.971, -0.8203) centre (-15.0597, -0.7998) ccw
  arc A141 (-15.0154, -0.8793) -> (-15.9739, -1.0335) centre (-14.5572, -6.7846) ccw
  line L197 (-14.9489, -1.7476) -> (-14.9786, -0.8781)
  line L198 (-14.9857, -1.7515) -> (-15.0154, -0.8793)
  line L199 (-15.9533, -1.6374) -> (-15.9739, -1.0335)
  arc A142 (-14.9448, -1.782) -> (-14.9857, -1.7515) centre (-14.999, -1.812) ccw
  arc A143 (-14.9393, -1.7954) -> (-14.9448, -1.782) centre (-14.999, -1.812) ccw
  arc A144 (-15.9533, -1.6374) -> (-14.9857, -1.7515) centre (-14.7783, 4.1679) ccw
  line L200 (-14.9489, -1.7476) -> (-14.7885, -2.545)
  line L201 (-14.7885, -2.545) -> (-14.7866, -2.5544)
  line L202 (-14.7866, -2.5544) -> (-14.7816, -2.5794)
  line L203 (-14.7754, -2.611) -> (-14.7832, -2.5594)
  arc A145 (-14.8118, -2.6166) -> (-14.7745, -2.5528) centre (-14.865, -2.5427) ccw
  arc A146 (-14.8118, -2.6166) -> (-15.7459, -2.8809) centre (-13.6711, -8.4287) ccw
  line L204 (-14.645, -3.4712) -> (-14.7754, -2.611)
  line L205 (-14.681, -3.4794) -> (-14.8118, -2.6166)
  line L206 (-15.6553, -3.4784) -> (-15.7459, -2.8809)
  arc A147 (-14.6368, -3.5049) -> (-14.681, -3.4794) centre (-14.6872, -3.5411) ccw
  arc A148 (-14.6299, -3.5176) -> (-14.6368, -3.5049) centre (-14.6872, -3.5411) ccw
  arc A149 (-15.6553, -3.4784) -> (-14.681, -3.4794) centre (-15.1623, 2.424) ccw
  line L207 (-14.645, -3.4712) -> (-14.3931, -4.2446)
  line L208 (-14.3931, -4.2446) -> (-14.3901, -4.2538)
  line L209 (-14.3901, -4.2538) -> (-14.3822, -4.278)
  line L210 (-14.3724, -4.3087) -> (-14.3861, -4.2583)
  arc A150 (-14.4079, -4.3184) -> (-14.3783, -4.2507) centre (-14.4693, -4.2512) ccw
  arc A151 (-14.4079, -4.3184) -> (-15.305, -4.6895) centre (-12.6002, -9.9588) ccw
  line L211 (-14.143, -5.1479) -> (-14.3724, -4.3087)
  line L212 (-14.1778, -5.1602) -> (-14.4079, -4.3184)
  line L213 (-15.1456, -5.2723) -> (-15.305, -4.6895)
  arc A152 (-14.131, -5.1805) -> (-14.1778, -5.1602) centre (-14.1768, -5.2222) ccw
  arc A153 (-14.1226, -5.1922) -> (-14.131, -5.1805) centre (-14.1768, -5.2222) ccw
  arc A154 (-15.1456, -5.2723) -> (-14.1778, -5.1602) centre (-15.3412, 0.6474) ccw
  line L214 (-14.143, -5.1479) -> (-13.803, -5.8868)
  line L215 (-13.803, -5.8868) -> (-13.799, -5.8956)
  line L216 (-13.799, -5.8956) -> (-13.7883, -5.9187)
  line L217 (-13.775, -5.9481) -> (-13.7945, -5.8997)
  arc A155 (-13.8092, -5.9619) -> (-13.7876, -5.8912) centre (-13.8779, -5.9022) ccw
  arc A156 (-13.8092, -5.9619) -> (-14.6571, -6.4345) centre (-11.3588, -11.3542) ccw
  line L218 (-13.4497, -6.755) -> (-13.775, -5.9481)
  line L219 (-13.4829, -6.7713) -> (-13.8092, -5.9619)
  line L220 (-14.4311, -6.995) -> (-14.6571, -6.4345)
  arc A157 (-13.434, -6.786) -> (-13.4829, -6.7713) centre (-13.4747, -6.8327) ccw
  arc A158 (-13.4243, -6.7966) -> (-13.434, -6.786) centre (-13.4747, -6.8327) ccw
  arc A159 (-14.4311, -6.995) -> (-13.4829, -6.7713) centre (-15.3126, -1.138) ccw
  line L221 (-13.4497, -6.755) -> (-13.0262, -7.4495)
  line L222 (-13.0262, -7.4495) -> (-13.0212, -7.4577)
  line L223 (-13.0212, -7.4577) -> (-13.008, -7.4794)
  line L224 (-12.9913, -7.507) -> (-13.0163, -7.4612)
  arc A160 (-13.0237, -7.5247) -> (-13.0104, -7.452) centre (-13.0989, -7.4735) ccw
  arc A161 (-13.0237, -7.5247) -> (-13.811, -8.0926) centre (-9.9639, -12.5961) ccw
  line L225 (-12.5745, -8.2707) -> (-12.9913, -7.507)
  line L226 (-12.6056, -8.2907) -> (-13.0237, -7.5247)
  line L227 (-13.5215, -8.6231) -> (-13.811, -8.0926)
  arc A162 (-12.5554, -8.2997) -> (-12.6056, -8.2907) centre (-12.5904, -8.3508) ccw
  arc A163 (-12.5445, -8.3091) -> (-12.5554, -8.2997) centre (-12.5904, -8.3508) ccw
  arc A164 (-13.5215, -8.6231) -> (-12.6056, -8.2907) centre (-15.077, -2.9079) ccw
  line L228 (-12.5745, -8.2707) -> (-12.0733, -8.9114)
  line L229 (-12.0733, -8.9114) -> (-12.0674, -8.9189)
  line L230 (-12.0674, -8.9189) -> (-12.0517, -8.939)
  line L231 (-12.0319, -8.9645) -> (-12.0621, -8.9219)
  arc A165 (-12.062, -8.9858) -> (-12.0573, -8.912) centre (-12.1427, -8.9436) ccw
  arc A166 (-12.062, -8.9858) -> (-12.7781, -9.6413) centre (-8.4342, -13.6677) ccw
  line L232 (-11.5293, -9.6746) -> (-12.0319, -8.9645)
  line L233 (-11.5579, -9.6981) -> (-12.062, -8.9858)
  line L234 (-12.429, -10.1345) -> (-12.7781, -9.6413)
  arc A167 (-11.5069, -9.7011) -> (-11.5579, -9.6981) centre (-11.5358, -9.756) ccw
  arc A168 (-11.495, -9.7093) -> (-11.5069, -9.7011) centre (-11.5358, -9.756) ccw
  arc A169 (-12.429, -10.1345) -> (-11.5579, -9.6981) centre (-14.6374, -4.6386) ccw
  line L235 (-11.5293, -9.6746) -> (-10.9571, -10.2527)
  line L236 (-10.9571, -10.2527) -> (-10.9504, -10.2596)
  line L237 (-10.9504, -10.2596) -> (-10.9325, -10.2777)
  line L238 (-10.9099, -10.3007) -> (-10.9448, -10.2619)
  arc A170 (-10.9373, -10.3253) -> (-10.9412, -10.2515) centre (-11.0223, -10.2928) ccw
  arc A171 (-10.9373, -10.3253) -> (-11.5724, -11.0595) centre (-6.7904, -14.5544) ccw
  line L239 (-10.3282, -10.9477) -> (-10.9099, -10.3007)
  line L240 (-10.3539, -10.9743) -> (-10.9373, -10.3253)
  line L241 (-11.1684, -11.5089) -> (-11.5724, -11.0595)
  arc A172 (-10.3029, -10.9714) -> (-10.3539, -10.9743) centre (-10.3252, -11.0293) ccw
  arc A173 (-10.2901, -10.9781) -> (-10.3029, -10.9714) centre (-10.3252, -11.0293) ccw
  arc A174 (-11.1684, -11.5089) -> (-10.3539, -10.9743) centre (-13.9999, -6.3065) ccw
  line L242 (-10.3282, -10.9477) -> (-9.6928, -11.4554)
  line L243 (-9.6928, -11.4554) -> (-9.6853, -11.4615)
  line L244 (-9.6853, -11.4615) -> (-9.6654, -11.4774)
  line L245 (-9.6403, -11.4976) -> (-9.6794, -11.4631)
  arc A175 (-9.6646, -11.5253) -> (-9.6771, -11.4524) centre (-9.7528, -11.5028) ccw
  arc A176 (-9.6646, -11.5253) -> (-10.2102, -12.3282) centre (-5.0548, -15.2443) ccw
  line L246 (-8.9874, -12.0727) -> (-9.6403, -11.4976)
  line L247 (-9.0098, -12.1021) -> (-9.6646, -11.5253)
  line L248 (-9.7568, -12.7276) -> (-10.2102, -12.3282)
  arc A177 (-8.9595, -12.0933) -> (-9.0098, -12.1021) centre (-8.9749, -12.1534) ccw
  arc A178 (-8.9461, -12.0985) -> (-8.9595, -12.0933) centre (-8.9749, -12.1534) ccw
  arc A179 (-9.7568, -12.7276) -> (-9.0098, -12.1021) centre (-13.1731, -7.8892) ccw
  line L249 (-8.9874, -12.0727) -> (-8.2974, -12.5033)
  line L250 (-8.2974, -12.5033) -> (-8.2892, -12.5084)
  line L251 (-8.2892, -12.5084) -> (-8.2676, -12.5218)
  line L252 (-8.2403, -12.539) -> (-8.2832, -12.5093)
  arc A180 (-8.2613, -12.5693) -> (-8.2821, -12.4984) centre (-8.3515, -12.5573) ccw
  arc A181 (-8.2613, -12.5693) -> (-8.71, -13.4302) centre (-3.2509, -15.7281) ccw
  line L253 (-7.5251, -13.0344) -> (-8.2403, -12.539)
  line L254 (-7.5439, -13.0663) -> (-8.2613, -12.5693)
  line L255 (-8.2132, -13.7743) -> (-8.71, -13.4302)
  arc A182 (-7.495, -13.0517) -> (-7.5439, -13.0663) centre (-7.5033, -13.1131) ccw
  arc A183 (-7.481, -13.0553) -> (-7.495, -13.0517) centre (-7.5033, -13.1131) ccw
  arc A184 (-8.2132, -13.7743) -> (-7.5439, -13.0663) centre (-12.1682, -9.3652) ccw
  line L256 (-7.5251, -13.0344) -> (-6.7897, -13.382)
  line L257 (-6.7897, -13.382) -> (-6.781, -13.3861)
  line L258 (-6.781, -13.3861) -> (-6.758, -13.397)
  line L259 (-6.7289, -13.4109) -> (-6.775, -13.3863)
  arc A185 (-6.7462, -13.4434) -> (-6.7751, -13.3754) centre (-6.8372, -13.4419) ccw
  arc A186 (-6.7462, -13.4434) -> (-7.0919, -14.3505) centre (-1.403, -15.9992) ccw
  line L260 (-5.961, -13.8199) -> (-6.7289, -13.4109)
  line L261 (-5.976, -13.8537) -> (-6.7462, -13.4434)
  line L262 (-6.5586, -14.6346) -> (-7.0919, -14.3505)
  arc A187 (-5.9291, -13.8336) -> (-5.976, -13.8537) centre (-5.9303, -13.8955) ccw
  arc A188 (-5.9148, -13.8355) -> (-5.9291, -13.8336) centre (-5.9303, -13.8955) ccw
  arc A189 (-6.5586, -14.6346) -> (-5.976, -13.8537) centre (-10.9987, -10.7145) ccw
  line L263 (-5.961, -13.8199) -> (-5.1902, -14.0797)
  line L264 (-5.1902, -14.0797) -> (-5.1811, -14.0828)
  line L265 (-5.1811, -14.0828) -> (-5.157, -14.0909)
  line L266 (-5.1265, -14.1014) -> (-5.1751, -14.0823)
  arc A190 (-5.1399, -14.1357) -> (-5.1765, -14.0715) centre (-5.2305, -14.1448) ccw
  arc A191 (-5.1399, -14.1357) -> (-5.378, -15.0768) centre (0.4639, -16.0539) ccw
  line L267 (-4.3163, -14.4185) -> (-5.1265, -14.1014)
  line L268 (-4.3273, -14.4538) -> (-5.1399, -14.1357)
  line L269 (-4.8153, -15.2971) -> (-5.378, -15.0768)
  arc A192 (-4.283, -14.4284) -> (-4.3273, -14.4538) centre (-4.277, -14.4901) ccw
  arc A193 (-4.2686, -14.4286) -> (-4.283, -14.4284) centre (-4.277, -14.4901) ccw
  arc A194 (-4.8153, -15.2971) -> (-4.3273, -14.4538) centre (-9.6804, -11.9189) ccw
  line L270 (-4.3163, -14.4185) -> (-3.5206, -14.5871)
  line L271 (-3.5206, -14.5871) -> (-3.5112, -14.5891)
  line L272 (-3.5112, -14.5891) -> (-3.4863, -14.5944)
  line L273 (-3.4547, -14.6012) -> (-3.5052, -14.5879)
  arc A195 (-3.4641, -14.6368) -> (-3.5079, -14.5773) centre (-3.553, -14.6564) ccw
  arc A196 (-3.4641, -14.6368) -> (-3.5913, -15.5992) centre (2.3245, -15.8915) ccw
  line L274 (-2.6133, -14.8221) -> (-3.4547, -14.6012)
  line L275 (-2.62, -14.8584) -> (-3.4641, -14.6368)
  line L276 (-3.0068, -15.7527) -> (-3.5913, -15.5992)
  arc A197 (-2.5791, -14.828) -> (-2.62, -14.8584) centre (-2.5659, -14.8886) ccw
  arc A198 (-2.5647, -14.8266) -> (-2.5791, -14.828) centre (-2.5659, -14.8886) ccw
  arc A199 (-3.0068, -15.7527) -> (-2.62, -14.8584) centre (-8.2313, -12.9621) ccw
  line L277 (-2.6133, -14.8221) -> (-1.8033, -14.8972)
  line L278 (-1.8033, -14.8972) -> (-1.7937, -14.8981)
  line L279 (-1.7937, -14.8981) -> (-1.7684, -14.9004)
  line L280 (-1.7363, -14.9035) -> (-1.788, -14.8962)
  arc A200 (-1.7415, -14.94) -> (-1.7919, -14.886) centre (-1.8275, -14.9697) ccw
  arc A201 (-1.7415, -14.94) -> (-1.7561, -15.9107) centre (4.1537, -15.5141) ccw
  line L281 (-0.8748, -15.0253) -> (-1.7363, -14.9035)
  line L282 (-0.8774, -15.0621) -> (-1.7415, -14.94)
  line L283 (-1.1577, -15.9952) -> (-1.7561, -15.9107)
  arc A202 (-0.8402, -15.0272) -> (-0.8774, -15.0621) centre (-0.8201, -15.0858) ccw
  arc A203 (-0.8261, -15.0241) -> (-0.8402, -15.0272) centre (-0.8201, -15.0858) ccw
  arc A204 (-1.1577, -15.9952) -> (-0.8774, -15.0621) centre (-6.6708, -13.8301) ccw
  line L284 (-0.8748, -15.0253) -> (-0.0617, -15.0058)
  line L285 (-0.0617, -15.0058) -> (-0.0521, -15.0056)
  line L286 (-0.0521, -15.0056) -> (-0.0266, -15.0049)
  line L287 (0.0056, -15.0043) -> (-0.0465, -15.0031)
  arc A205 (0.0048, -15.0412) -> (-0.0516, -14.9934) centre (-0.0772, -15.0807) ccw
  arc A206 (0.0048, -15.0412) -> (0.1029, -16.0069) centre (5.9267, -14.927) ccw
  line L288 (0.8754, -15.0252) -> (0.0056, -15.0043)
  line L289 (0.8772, -15.0621) -> (0.0048, -15.0412)
  line L290 (0.707, -16.0215) -> (0.1029, -16.0069)
  arc A207 (0.91, -15.0231) -> (0.8772, -15.0621) centre (0.9368, -15.079) ccw
  arc A208 (0.9237, -15.0184) -> (0.91, -15.0231) centre (0.9368, -15.079) ccw
  arc A209 (0.707, -16.0215) -> (0.8772, -15.0621) centre (-5.0201, -14.511) ccw
  line L291 (0.8754, -15.0252) -> (1.6808, -14.9115)
  line L292 (1.6808, -14.9115) -> (1.6903, -14.9101)
  line L293 (1.6903, -14.9101) -> (1.7155, -14.9066)
  line L294 (1.7475, -14.9022) -> (1.6955, -14.907)
  arc A210 (1.7509, -14.9389) -> (1.6894, -14.898) centre (1.6741, -14.9877) ccw
  arc A211 (1.7509, -14.9389) -> (1.9605, -15.8868) centre (7.6195, -14.1381) ccw
  line L295 (2.6138, -14.822) -> (1.7475, -14.9022)
  line L296 (2.6199, -14.8585) -> (1.7509, -14.9389)
  line L297 (2.5622, -15.8311) -> (1.9605, -15.8868)
  arc A212 (2.648, -14.8159) -> (2.6199, -14.8585) centre (2.6811, -14.8683) ccw
  arc A213 (2.661, -14.8096) -> (2.648, -14.8159) centre (2.6811, -14.8683) ccw
  arc A214 (2.5622, -15.8311) -> (2.6199, -14.8585) centre (-3.3016, -14.9957) ccw
  line L298 (2.6138, -14.822) -> (3.4005, -14.6155)
  line L299 (3.4005, -14.6155) -> (3.4099, -14.6131)
  line L300 (3.4099, -14.6131) -> (3.4345, -14.6066)
  line L301 (3.4657, -14.5986) -> (3.4147, -14.6094)
  arc A215 (3.4734, -14.6346) -> (3.4075, -14.6011) centre (3.4027, -14.692) ccw
  arc A216 (3.4734, -14.6346) -> (3.7916, -15.5517) centre (9.2093, -13.1579) ccw
  line L302 (4.3169, -14.4184) -> (3.4657, -14.5986)
  line L303 (4.3271, -14.4539) -> (3.4734, -14.6346)
  line L304 (4.3828, -15.4266) -> (3.7916, -15.5517)
  arc A217 (4.3501, -14.4083) -> (4.3271, -14.4539) centre (4.389, -14.4565) ccw
  arc A218 (4.3623, -14.4006) -> (4.3501, -14.4083) centre (4.389, -14.4565) ccw
  arc A219 (4.3828, -15.4266) -> (4.3271, -14.4539) centre (-1.5383, -15.2776) ccw
  line L305 (4.3169, -14.4184) -> (5.0743, -14.1219)
  line L306 (5.0743, -14.1219) -> (5.0833, -14.1184)
  line L307 (5.0833, -14.1184) -> (5.107, -14.1091)
  line L308 (5.1371, -14.0975) -> (5.0876, -14.1142)
  arc A220 (5.1488, -14.1324) -> (5.0795, -14.1068) centre (5.0853, -14.1976) ccw
  arc A221 (5.1488, -14.1324) -> (5.5714, -15.0064) centre (10.6746, -11.9998) ccw
  line L309 (5.9615, -13.8197) -> (5.1371, -14.0975)
  line L310 (5.9758, -13.8538) -> (5.1488, -14.1324)
  line L311 (6.1441, -14.8134) -> (5.5714, -15.0064)
  arc A222 (5.9934, -13.8058) -> (5.9758, -13.8538) centre (6.0377, -13.8492) ccw
  arc A223 (6.0046, -13.7968) -> (5.9934, -13.8058) centre (6.0377, -13.8492) ccw
  arc A224 (6.1441, -14.8134) -> (5.9758, -13.8538) centre (0.2457, -15.3529) ccw
  line L312 (5.9615, -13.8197) -> (6.6795, -13.4373)
  line L313 (6.6795, -13.4373) -> (6.688, -13.4328)
  line L314 (6.688, -13.4328) -> (6.7104, -13.4208)
  line L315 (6.739, -13.4058) -> (6.6918, -13.4281)
  arc A225 (6.7547, -13.4391) -> (6.6829, -13.4217) centre (6.6992, -13.5112) ccw
  arc A226 (6.7547, -13.4391) -> (7.2759, -14.2581) centre (11.9955, -10.6794) ccw
  line L316 (7.5256, -13.0342) -> (6.739, -13.4058)
  line L317 (7.5438, -13.0664) -> (6.7547, -13.4391)
  line L318 (7.8223, -14) -> (7.2759, -14.2581)
  arc A227 (7.5556, -13.0167) -> (7.5438, -13.0664) centre (7.6046, -13.0546) ccw
  arc A228 (7.5657, -13.0064) -> (7.5556, -13.0167) centre (7.6046, -13.0546) ccw
  arc A229 (7.8223, -14) -> (7.5438, -13.0664) centre (2.0264, -15.2205) ccw
  line L319 (7.5256, -13.0342) -> (8.1943, -12.5711)
  line L320 (8.1943, -12.5711) -> (8.2022, -12.5656)
  line L321 (8.2022, -12.5656) -> (8.2231, -12.5511)
  line L322 (8.2497, -12.5328) -> (8.2054, -12.5605)
  arc A230 (8.2692, -12.5641) -> (8.1959, -12.5551) centre (8.2225, -12.6422) ccw
  arc A231 (8.2692, -12.5641) -> (8.882, -13.317) centre (13.1542, -9.2146) ccw
  line L323 (8.9879, -12.0724) -> (8.2497, -12.5328)
  line L324 (9.0097, -12.1022) -> (8.2692, -12.5641)
  line L325 (9.3947, -12.9972) -> (8.882, -13.317)
  arc A232 (9.0157, -12.0515) -> (9.0097, -12.1022) centre (9.0688, -12.0835) ccw
  arc A233 (9.0245, -12.0401) -> (9.0157, -12.0515) centre (9.0688, -12.0835) ccw
  arc A234 (9.3947, -12.9972) -> (9.0097, -12.1022) centre (3.7797, -14.8824) ccw
  line L326 (8.9879, -12.0724) -> (9.5983, -11.5348)
  line L327 (9.5983, -11.5348) -> (9.6055, -11.5284)
  line L328 (9.6055, -11.5284) -> (9.6246, -11.5116)
  line L329 (9.6489, -11.4903) -> (9.6081, -11.5229)
  arc A235 (9.6719, -11.5191) -> (9.598, -11.5187) centre (9.6345, -11.6021) ccw
  arc A236 (9.6719, -11.5191) -> (10.3679, -12.1959) centre (14.135, -7.6252) ccw
  line L330 (10.3286, -10.9473) -> (9.6489, -11.4903)
  line L331 (10.3537, -10.9744) -> (9.6719, -11.5191)
  line L332 (10.84, -11.8187) -> (10.3679, -12.1959)
  arc A237 (10.3538, -10.9234) -> (10.3537, -10.9744) centre (10.4103, -10.949) ccw
  arc A238 (10.3612, -10.911) -> (10.3538, -10.9234) centre (10.4103, -10.949) ccw
  arc A239 (10.84, -11.8187) -> (10.3537, -10.9744) centre (5.4819, -14.3429) ccw
  line L333 (10.3286, -10.9473) -> (10.8725, -10.3425)
  line L334 (10.8725, -10.3425) -> (10.8789, -10.3353)
  line L335 (10.8789, -10.3353) -> (10.8959, -10.3164)
  line L336 (10.9176, -10.2925) -> (10.8809, -10.3296)
  arc A240 (10.9438, -10.3184) -> (10.8704, -10.3266) centre (10.9163, -10.4052) ccw
  arc A241 (10.9438, -10.3184) -> (11.7137, -10.9098) centre (14.9246, -5.9327) ccw
  line L337 (11.5297, -9.6742) -> (10.9176, -10.2925)
  line L338 (11.5578, -9.6982) -> (10.9438, -10.3184)
  line L339 (12.1388, -10.4803) -> (11.7137, -10.9098)
  arc A242 (11.5519, -9.6475) -> (11.5578, -9.6982) centre (11.611, -9.6664) ccw
  arc A243 (11.5579, -9.6344) -> (11.5519, -9.6475) centre (11.611, -9.6664) ccw
  arc A244 (12.1388, -10.4803) -> (11.5578, -9.6982) centre (7.1099, -13.6096) ccw
  line L340 (11.5297, -9.6742) -> (11.9997, -9.0103)
  line L341 (11.9997, -9.0103) -> (12.0052, -9.0025)
  line L342 (12.0052, -9.0025) -> (12.0199, -8.9817)
  line L343 (12.0387, -8.9554) -> (12.0065, -8.9965)
  arc A245 (12.0677, -8.9781) -> (11.9957, -8.9948) centre (12.0505, -9.0675) ccw
  arc A246 (12.0677, -8.9781) -> (12.901, -9.4761) centre (15.5125, -4.1599) ccw
  line L344 (12.5748, -8.2703) -> (12.0387, -8.9554)
  line L345 (12.6055, -8.2909) -> (12.0677, -8.9781)
  line L346 (13.2734, -9.0002) -> (12.901, -9.4761)
  arc A247 (12.5938, -8.2412) -> (12.6055, -8.2909) centre (12.6547, -8.2531) ccw
  arc A248 (12.5982, -8.2275) -> (12.5938, -8.2412) centre (12.6547, -8.2531) ccw
  arc A249 (13.2734, -9.0002) -> (12.6055, -8.2909) centre (8.6418, -12.6921) ccw
  line L347 (12.5748, -8.2703) -> (12.9646, -7.5563)
  line L348 (12.9646, -7.5563) -> (12.9692, -7.5479)
  line L349 (12.9692, -7.5479) -> (12.9814, -7.5255)
  line L350 (12.9969, -7.4973) -> (12.9698, -7.5418)
  arc A250 (13.0284, -7.5165) -> (12.9588, -7.5414) centre (13.0216, -7.6072) ccw
  arc A251 (13.0284, -7.5165) -> (13.9139, -7.9143) centre (15.8905, -2.3309) ccw
  line L351 (13.4499, -6.7545) -> (12.9969, -7.4973)
  line L352 (13.4828, -6.7714) -> (13.0284, -7.5165)
  line L353 (14.2285, -7.3984) -> (13.9139, -7.9143)
  arc A252 (13.4654, -6.7234) -> (13.4828, -6.7714) centre (13.5272, -6.7282) ccw
  arc A253 (13.4682, -6.7093) -> (13.4654, -6.7234) centre (13.5272, -6.7282) ccw
  arc A254 (14.2285, -7.3984) -> (13.4828, -6.7714) centre (10.0568, -11.6031) ccw
  line L354 (13.4499, -6.7545) -> (13.7541, -6.0001)
  line L355 (13.7541, -6.0001) -> (13.7577, -5.9912)
  line L356 (13.7577, -5.9912) -> (13.7672, -5.9676)
  line L357 (13.7794, -5.9377) -> (13.7576, -5.9852)
  arc A255 (13.8129, -5.9531) -> (13.7467, -5.9859) centre (13.8167, -6.0441) ccw
  arc A256 (13.8129, -5.9531) -> (14.7386, -6.2455) centre (16.0537, -0.4703) ccw
  line L358 (14.1431, -5.1474) -> (13.7794, -5.9377)
  line L359 (14.1777, -5.1604) -> (13.8129, -5.9531)
  line L360 (14.9912, -5.6966) -> (14.7386, -6.2455)
  arc A257 (14.1549, -5.1147) -> (14.1777, -5.1604) centre (14.2169, -5.1123) ccw
  arc A258 (14.156, -5.1004) -> (14.1549, -5.1147) centre (14.2169, -5.1123) ccw
  arc A259 (14.9912, -5.6966) -> (14.1777, -5.1604) centre (11.3359, -10.3571) ccw
  line L361 (14.1431, -5.1474) -> (14.3577, -4.3628)
  line L362 (14.3577, -4.3628) -> (14.3602, -4.3535)
  line L363 (14.3602, -4.3535) -> (14.367, -4.329)
  line L364 (14.3756, -4.2979) -> (14.3594, -4.3475)
  arc A260 (14.4106, -4.3093) -> (14.3487, -4.3496) centre (14.425, -4.3992) ccw
  arc A261 (14.4106, -4.3093) -> (15.364, -4.4922) centre (15.9997, 1.3966) ccw
  line L365 (14.6451, -3.4707) -> (14.3756, -4.2979)
  line L366 (14.681, -3.4795) -> (14.4106, -4.3093)
  line L367 (15.5512, -3.9177) -> (15.364, -4.4922)
  arc A262 (14.653, -3.4369) -> (14.681, -3.4795) centre (14.7142, -3.4272) ccw
  arc A263 (14.6524, -3.4225) -> (14.653, -3.4369) centre (14.7142, -3.4272) ccw
  arc A264 (15.5512, -3.9177) -> (14.681, -3.4795) centre (12.4616, -8.971) ccw
  line L368 (14.6451, -3.4707) -> (14.7671, -2.6665)
  line L369 (14.7671, -2.6665) -> (14.7685, -2.657)
  line L370 (14.7685, -2.657) -> (14.7724, -2.6318)
  line L371 (14.7774, -2.5999) -> (14.7671, -2.6511)
  arc A265 (14.8135, -2.6072) -> (14.7566, -2.6544) centre (14.8382, -2.6948) ccw
  arc A266 (14.8135, -2.6072) -> (15.7816, -2.6782) centre (15.7294, 3.2446) ccw
  line L372 (14.949, -1.747) -> (14.7774, -2.5999)
  line L373 (14.9856, -1.7517) -> (14.8135, -2.6072)
  line L374 (15.9009, -2.0858) -> (15.7816, -2.6782)
  arc A267 (14.9529, -1.7125) -> (14.9856, -1.7517) centre (15.0126, -1.6958) ccw
  arc A268 (14.9507, -1.6983) -> (14.9529, -1.7125) centre (15.0126, -1.6958) ccw
  arc A269 (15.9009, -2.0858) -> (14.9856, -1.7517) centre (13.4188, -7.4637) ccw
  line L375 (14.949, -1.747) -> (14.9768, -0.9341)
  line L376 (14.9768, -0.9341) -> (14.9771, -0.9245)
  line L377 (14.9771, -0.9245) -> (14.978, -0.899)
  point P0 (0, 0)
  point P1 (15.015, -0.4333)
  point P2 (0, 0)
  point P3 (14.9764, -0.9014)
  point P4 (0, 0)
  point P5 (15.0174, 0.4056)
  point P6 (14.9638, 1.3128)
  point P7 (14.8687, 2.1463)
  point P8 (0, 0)
  point P9 (0, 0)
  point P10 (14.7102, 3.0411)
  point P11 (14.519, 3.8579)
  point P12 (0, 0)
  point P13 (0, 0)
  point P14 (14.2577, 4.7283)
  point P15 (13.973, 5.5174)
  point P16 (0, 0)
  point P17 (0, 0)
  point P18 (13.6123, 6.3515)
  point P19 (13.238, 7.1022)
  point P20 (0, 0)
  point P21 (0, 0)
  point P22 (12.7829, 7.8889)
  point P23 (12.3239, 8.591)
  point P24 (0, 0)
  point P25 (0, 0)
  point P26 (11.7806, 9.3196)
  point P27 (11.2432, 9.9637)
  point P28 (0, 0)
  point P29 (0, 0)
  point P30 (10.6191, 10.6242)
  point P31 (10.0105, 11.2016)
  point P32 (0, 0)
  point P33 (0, 0)
  point P34 (9.3139, 11.7852)
  point P35 (8.6424, 12.288)
  point P36 (0, 0)
  point P37 (0, 0)
  point P38 (7.8827, 12.7867)
  point P39 (7.1574, 13.2082)
  point P40 (0, 0)
  point P41 (0, 0)
  point P42 (6.345, 13.6154)
  point P43 (5.5756, 13.9498)
  point P44 (0, 0)
  point P45 (0, 0)
  point P46 (4.7214, 14.2599)
  point P47 (3.9185, 14.5028)
  point P48 (0, 0)
  point P49 (0, 0)
  point P50 (3.034, 14.7116)
  point P51 (2.2083, 14.8596)
  point P52 (0, 0)
  point P53 (0, 0)
  point P54 (1.3056, 14.9644)
  point P55 (0.4683, 15.0155)
  point P56 (0, 0)
  point P57 (0, 0)
  point P58 (-0.4405, 15.0148)
  point P59 (-1.2781, 14.9684)
  point P60 (0, 0)
  point P61 (0, 0)
  point P62 (-2.1807, 14.8621)
  point P63 (-3.0072, 14.7188)
  point P64 (0, 0)
  point P65 (0, 0)
  point P66 (-3.8913, 14.5085)
  point P67 (-4.6956, 14.2701)
  point P68 (0, 0)
  point P69 (0, 0)
  point P70 (-5.5493, 13.9586)
  point P71 (-6.3205, 13.6285)
  point P72 (0, 0)
  point P73 (0, 0)
  point P74 (-7.1323, 13.22)
  point P75 (-7.8599, 12.8026)
  point P76 (0, 0)
  point P77 (0, 0)
  point P78 (-8.6188, 12.3026)
  point P79 (-9.2931, 11.8036)
  point P80 (0, 0)
  point P81 (0, 0)
  point P82 (-9.9888, 11.2188)
  point P83 (-10.6006, 10.6449)
  point P84 (0, 0)
  point P85 (0, 0)
  point P86 (-11.2237, 9.9833)
  point P87 (-11.7647, 9.3423)
  point P88 (0, 0)
  point P89 (0, 0)
  point P90 (-12.3068, 8.6129)
  point P91 (-12.7697, 7.9133)
  point P92 (0, 0)
  point P93 (0, 0)
  point P94 (-13.2234, 7.1259)
  point P95 (-13.602, 6.3773)
  point P96 (0, 0)
  point P97 (0, 0)
  point P98 (-13.9613, 5.5426)
  point P99 (-14.2504, 4.7551)
  point P100 (0, 0)
  point P101 (0, 0)
  point P102 (-14.5103, 3.8843)
  point P103 (-14.7061, 3.0686)
  point P104 (0, 0)
  point P105 (0, 0)
  point P106 (-14.8632, 2.1735)
  point P107 (-14.9629, 1.3406)
  point P108 (0, 0)
  point P109 (0, 0)
  point P110 (-15.015, 0.4333)
  point P111 (-15.0174, -0.4056)
  point P112 (0, 0)
  point P113 (0, 0)
  point P114 (-14.9638, -1.3128)
  point P115 (-14.8687, -2.1463)
  point P116 (0, 0)
  point P117 (0, 0)
  point P118 (-14.7102, -3.0411)
  point P119 (-14.519, -3.8579)
  point P120 (0, 0)
  point P121 (0, 0)
  point P122 (-14.2577, -4.7283)
  point P123 (-13.973, -5.5174)
  point P124 (0, 0)
  point P125 (0, 0)
  point P126 (-13.6123, -6.3515)
  point P127 (-13.238, -7.1022)
  point P128 (0, 0)
  point P129 (0, 0)
  point P130 (-12.7829, -7.8889)
  point P131 (-12.3239, -8.591)
  point P132 (0, 0)
  point P133 (0, 0)
  point P134 (-11.7806, -9.3196)
  point P135 (-11.2432, -9.9637)
  point P136 (0, 0)
  point P137 (0, 0)
  point P138 (-10.6191, -10.6242)
  point P139 (-10.0105, -11.2016)
  point P140 (0, 0)
  point P141 (0, 0)
  point P142 (-9.3139, -11.7852)
  point P143 (-8.6424, -12.288)
  point P144 (0, 0)
  point P145 (0, 0)
  point P146 (-7.8827, -12.7867)
  point P147 (-7.1574, -13.2082)
  point P148 (0, 0)